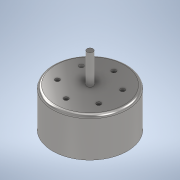
# Autodesk Inventor part: 300电机
Saved by Autodesk Inventor 2021.4 (Build 254397000, 397)
## iProperties
Created: 2024-04-09
Part Number: 300电机
Material: 不锈钢
Document SubType Name: Modeling
Designer: PC
Density: 8 g/cm^3
Appearance: 半抛光
Author: PC
Autodesk Inventor part; units mm, degrees
ref_plane "YZ Plane" through (0, 0, 0) normal (1, 0, 0) x (0, 1, 0)
ref_plane "XZ Plane" through (0, 0, 0) normal (0, 1, 0) x (-1, 0, 0)
ref_plane "XY Plane" through (0, 0, 0) normal (0, 0, 1) x (1, 0, 0)
sketch "草图1" plane through (0, 0, 0) normal (0, 1, 0) x (-1, 0, 0)
  circle A0 centre (0, 0) radius 12.5
  dimension "d0" = 25
  constraints: 1 centre point, 1 coincident
  measures "d0" diameter of A0
extrude "拉伸1" add sketch "草图1" along normal blind 13
fillet "圆角1" radius 1 1 edges at (12.5, 13, 0)
sketch "草图2" plane through (0, 13, 0) normal (0, 1, 0) x (1, 0, 0)
  circle A0 centre (0, 0) radius 1
  dimension "d4" = 2
  constraints: 1 centre point, 1 coincident
  measures "d4" diameter of A0
extrude "拉伸2" add sketch "草图2" along normal blind 10
sketch "草图3" plane through (0, 13, 0) normal (0, 1, 0) x (1, 0, 0)
  circle A0 centre (0, 8) radius 0.75
  point P0 (0, 0)
  dimension "d7" = 1.5
  dimension "d8" = 8
  constraints: 1 centre point
  measures "d7" diameter of A0
  measures "d8" distance of point (0, 0) A0.centre
extrude "拉伸3" cut sketch "草图3" against normal blind 5
pattern_circular "环形阵列1" count 6 over 360 about axis through (0, 12, 0) along (0, 1, 0) of "拉伸3"
